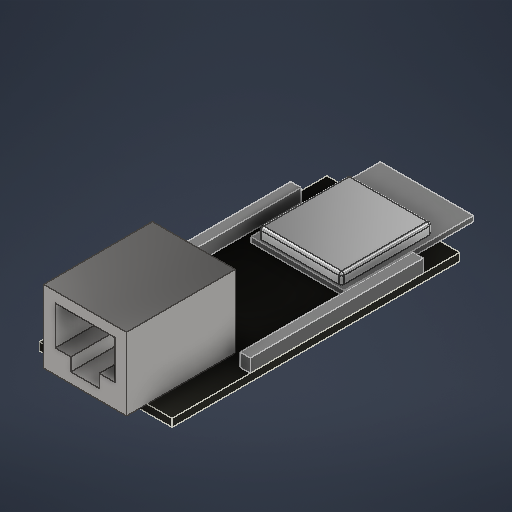
# Autodesk Inventor part: ETH32
Saved by Autodesk Inventor 2027.1 (Build 311270010, 270A)
## iProperties
Created: 2026-09-27
Part Number: ETH32
Material: 열가소성 수지
Document SubType Name: Modeling
Designer: work
Density: 1.28 g/cm^3
Appearance: 매끄러움 - 검은색
Author: work
Autodesk Inventor part; units mm, degrees
ref_plane "YZ Plane" through (0, 0, 0) normal (1, 0, 0) x (0, 1, 0)
ref_plane "XZ Plane" through (0, 0, 0) normal (0, 1, 0) x (-1, 0, 0)
ref_plane "XY Plane" through (0, 0, 0) normal (0, 0, 1) x (1, 0, 0)
sketch "스케치1" plane through (0, 0, 0) normal (0, 1, 0) x (-1, 0, 0)
  line L0 (0, 0) -> (25.6, 0)
  line L1 (25.6, 0) -> (25.6, -55.5)
  line L2 (25.6, -55.5) -> (0, -55.5)
  line L3 (0, -55.5) -> (0, 0)
  dimension "d0" = 25.6
  dimension "d1" = 55.5
  constraints: 8 end point, 2 parallel, 1 horizontal, 1 perpendicular
  measures "d0" distance of L1.end L2.end
  measures "d1" distance of L0.end L1.end
extrude "돌출1" add sketch "스케치1" along normal blind 1.5
sketch "스케치2" plane through (0, 1.5, 0) normal (0, 1, 0) x (1, 0, 0)
  line L0 (-20.8, -4) -> (-4.8, -4)
  line L1 (-4.8, -4) -> (-4.8, 17)
  line L2 (-4.8, 17) -> (-20.8, 17)
  line L3 (-20.8, 17) -> (-20.8, -4)
  line L4 (-25.6, 0) -> (0, 0) projected
  point P0 (-12.8, 17)
  point P1 (-12.8, 0)
  point P2 (-12.8, -4)
  dimension "d4" = 16
  dimension "d5" = 21
  dimension "d6" = 4
  constraints: 8 end point, 3 midpoint, 2 parallel, 1 horizontal, 1 perpendicular, 1 vertical alignment
  measures "d4" distance of L2.end L1.end
  measures "d5" distance of L1.end L0.end
  measures "d6" distance of point (-12.8, -4) point (-12.8, 0)
extrude "돌출2" add sketch "스케치2" along normal blind 14 separate body
sketch "스케치3" plane through (-20.8, 1.5, 4) normal (0, 0, 1) x (1, 0, 0)
  line L0 (2.25, 2) -> (13.75, 2)
  line L1 (13.75, 2) -> (13.75, 12)
  line L2 (13.75, 12) -> (2.25, 12)
  line L3 (2.25, 12) -> (2.25, 2)
  line L4 (2.25, 2) -> (5.25, 2)
  line L5 (5.25, 2) -> (5.25, 4.5)
  line L6 (5.25, 4.5) -> (2.25, 4.5)
  line L7 (2.25, 4.5) -> (2.25, 2)
  line L8 (8, 2) -> (8, 12) construction
  line L9 (10.75, 2) -> (10.75, 4.5)
  line L10 (10.75, 4.5) -> (13.75, 4.5)
  line L11 (16, 0) -> (16, 14) projected
  line L12 (0, 14) -> (16, 14) projected
  point P0 (20.8, -1.5)
  point P1 (13.75, 7)
  point P2 (16, 7)
  point P3 (8, 14)
  point P4 (5.25, 2)
  point P5 (10.75, 2)
  dimension "d9" = 11.5
  dimension "d10" = 10
  dimension "d11" = 3
  dimension "d12" = 2.5
  constraints: 22 end point, 5 midpoint, 4 parallel, 3 symmetric about line, 2 horizontal, 2 perpendicular, 1 horizontal alignment, 1 vertical alignment
  measures "d9" distance of L2.end L1.end
  measures "d10" distance of L1.end L0.end
  measures "d11" distance of L6.end L5.end
  measures "d12" distance of L5.end L4.end
extrude "돌출3" cut sketch "스케치3" against normal blind 20 contours L5 L6 L3 L2 L1 L10 L9 L0 bodies 2
sketch "스케치4" plane through (0, 1.5, 0) normal (0, 1, 0) x (1, 0, 0)
  line L0 (-2, 15.1) -> (0, 15.1)
  line L1 (0, 15.1) -> (0, 48.5)
  line L2 (0, 48.5) -> (-2, 48.5)
  line L3 (-2, 48.5) -> (-2, 15.1)
  line L4 (0, 0) -> (0, 55.5) projected
  line L5 (0, 55.5) -> (-25.6, 55.5) projected
  line L6 (-4.8, 17) -> (-20.8, 17) projected
  line L7 (-12.8, 17) -> (-12.8, 55.5) construction
  line L8 (0, 55.5) -> (-25.6, 55.5) projected
  line L9 (-25.6, 55.5) -> (-25.6, 0) projected
  line L10 (-25.6, 0) -> (0, 0) projected
  line L11 (0, 0) -> (0, 55.5) projected
  line L12 (-23.6, 15.1) -> (-25.6, 15.1)
  line L13 (-25.6, 48.5) -> (-23.6, 48.5)
  line L14 (-23.6, 48.5) -> (-23.6, 15.1)
  point P0 (-1, 48.5)
  dimension "d15" = 2
  dimension "d16" = 33.4
  dimension "d17" = 7
  constraints: 16 end point, 4 symmetric about line, 3 midpoint, 2 parallel, 1 horizontal, 1 perpendicular, 1 point on line
  measures "d15" distance of L2.end L1.end
  measures "d16" distance of L1.end L0.end
  measures "d17" distance from line of L5 point (-1, 48.5)
extrude "돌출4" add sketch "스케치4" along normal blind 2.54 separate body contours L3 L2 L1 L0 | L9 L13 L14 L12
sketch "스케치5" plane through (0, 1.5, 0) normal (0, 1, 0) x (1, 0, 0)
  line L0 (-21.8, 37) -> (-3.8, 37)
  line L1 (-3.8, 37) -> (-3.8, 62)
  line L2 (-3.8, 62) -> (-21.8, 62)
  line L3 (-21.8, 62) -> (-21.8, 37)
  line L4 (0, 55.5) -> (-25.6, 55.5) projected
  point P0 (0, 0)
  point P1 (-12.8, 55.5)
  point P2 (-12.8, 62)
  dimension "d20" = 18
  dimension "d21" = 25
  dimension "d22" = 6.5
  constraints: 8 end point, 2 midpoint, 2 parallel, 1 horizontal, 1 perpendicular, 1 vertical alignment
  measures "d20" distance of L2.end L1.end
  measures "d21" distance of L1.end L0.end
  measures "d22" distance between parallel lines of L2 L4
extrude "돌출5" add sketch "스케치5" along normal blind 1 separate body
sketch "스케치6" plane through (0, 2.5, 0) normal (0, 1, 0) x (1, 0, 0)
  line L0 (-20.8, 37.5) -> (-4.8, 37.5)
  line L1 (-4.8, 37.5) -> (-4.8, 55)
  line L2 (-4.8, 55) -> (-20.8, 55)
  line L3 (-20.8, 55) -> (-20.8, 37.5)
  line L4 (-21.8, 37) -> (-3.8, 37) projected
  point P0 (0, 0)
  point P1 (-12.8, 37.5)
  point P2 (-12.8, 37)
  dimension "d25" = 17.5
  dimension "d26" = 16
  dimension "d27" = 0.5
  constraints: 8 end point, 2 midpoint, 2 parallel, 1 horizontal, 1 perpendicular, 1 vertical alignment
  measures "d25" distance of L2.end L0.start
  measures "d26" distance of L0.start L0.end
  measures "d27" distance between parallel lines of L4 L0
extrude "돌출6" add sketch "스케치6" along normal blind 2 separate body
fillet "모깎기1" radius 0.5 4 edges at (-4.8, 3.5, -37.5) (-4.8, 3.5, -55) (-20.8, 3.5, -55) (-20.8, 3.5, -37.5)
fillet "모깎기2" radius 0.5 8 edges at (-4.9464, 4.5, -37.6464) (-4.8, 4.5, -46.25) (-4.9464, 4.5, -54.8536) (-12.8, 4.5, -55) (-20.6536, 4.5, -54.8536) (-20.8, 4.5, -46.25) (-20.6536, 4.5, -37.6464) (-12.8, 4.5, -37.5)
